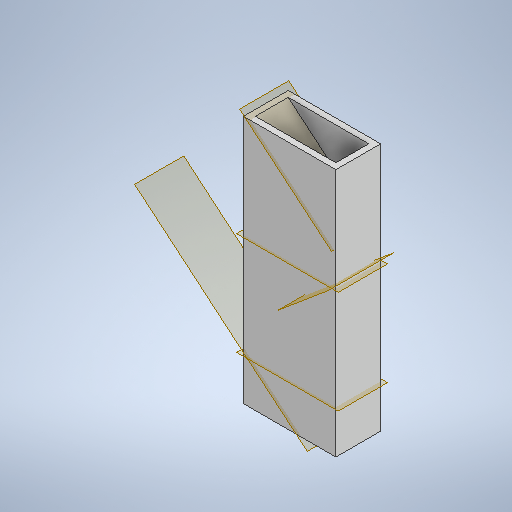
# Autodesk Inventor part: Semesterprojekt1magnetpakholdermedden_med_den_lange_side
Saved by Autodesk Inventor 2027.1 (Build 311270010, 270A)
## iProperties
Created: 2026-10-27
Part Number: Semesterprojekt1magnetpakholdermedden_med_den_lange_side
Material: Generic
Document SubType Name: Modeling
Designer: Sif Isaksen
Density: 1 g/cm^3
Appearance: Default
Author: Sif Isaksen
Autodesk Inventor part; units mm, degrees
ref_plane "YZ Plane" through (0, 0, 0) normal (1, 0, 0) x (0, 1, 0)
ref_plane "XZ Plane" through (0, 0, 0) normal (0, 1, 0) x (-1, 0, 0)
ref_plane "XY Plane" through (0, 0, 0) normal (0, 0, 1) x (1, 0, 0)
sketch "Sketch1" plane through (0, 0, 0) normal (0, 1, 0) x (-1, 0, 0)
  line L0 (11.8062, 10.4849) -> (-15.1938, 10.4849)
  line L1 (-15.1938, 10.4849) -> (-15.1938, -0.5151)
  line L2 (-15.1938, -0.5151) -> (11.8062, -0.5151)
  line L3 (11.8062, -0.5151) -> (11.8062, 10.4849)
  line L4 (13.8062, 12.4849) -> (-17.1938, 12.4849)
  line L5 (-17.1938, 12.4849) -> (-17.1938, -2.5151)
  line L6 (-17.1938, -2.5151) -> (13.8062, -2.5151)
  line L7 (13.8062, -2.5151) -> (13.8062, 12.4849)
  point P0 (0, 0)
  dimension "d0" = 27
  dimension "d1" = 11
  dimension "d2" = 31
  dimension "d3" = 15
  dimension "d4" = 2
  dimension "d5" = 2
  constraints: 16 end point, 4 parallel, 2 horizontal, 2 perpendicular
  measures "d0" distance of L2.end L1.end
  measures "d1" distance of L1.end L0.end
  measures "d2" distance of L6.end L5.end
  measures "d3" distance of L5.end L4.end
  measures "d4" distance between parallel lines of L3 L7
  measures "d5" distance between parallel lines of L4 L0
extrude "Extrusion1" add sketch "Sketch1" along normal blind 20 and the other way blind 63.5
ref_plane "Work Plane1" through (-11.8062, 20, 10.4849) normal (0.6428, 0.766, 0) x (0, 0, -1)
sketch "Sketch2" plane through (-11.8062, 20, 10.4849) normal (0.6428, 0.766, 0) x (0, 0, -1)
  line L0 (0, 0) -> (11, 0) projected
  line L1 (0, 0) -> (11, 0)
  line L2 (11, 0) -> (11, -21)
  line L3 (11, -21) -> (0, -21)
  line L4 (0, -21) -> (0, 0)
  point P0 (10.4849, -21.8998)
  dimension "d9" = 11
  dimension "d10" = 21
  constraints: 8 end point, 2 parallel, 1 horizontal, 1 perpendicular
  measures "d9" distance of L2.end L3.end
  measures "d10" distance of L1.end L2.end
extrude "Extrusion2" add sketch "Sketch2" against normal blind 1
sketch "Sketch3" plane through (0, -63.5, 0) normal (0, -1, 0) x (1, 0, 0)
  point P0 (0, 0)
sketch "Sketch4" plane through (0, -63.5, 0) normal (0, -1, 0) x (1, 0, 0)
  point P0 (0, 0)
ref_plane "Work Plane2" through (0, -14.5, 0) normal (0, 1, 0) x (1, 0, 0)
ref_plane "Work Plane5" through (15.1938, -14.5, 10.4849) normal (-0.6428, 0.766, 0) x (0, 0, -1)
sketch "Sketch8" plane through (15.1938, -14.5, 10.4849) normal (-0.6428, 0.766, 0) x (0, 0, -1)
  point P0 (10.4849, 2.3187)
ref_plane "Work Plane6" through (15.1938, -14.5, 10.4849) normal (-0.6428, 0.766, 0) x (0, 0, -1)
sketch "Sketch9" plane through (15.1938, -14.5, 10.4849) normal (-0.6428, 0.766, 0) x (0, 0, -1)
  line L0 (11, 3.5353) -> (11, -22.1762) projected
  line L1 (11, 0) -> (0, 0)
  line L2 (0, 0) -> (0, 21)
  line L3 (0, 21) -> (11, 21)
  line L4 (11, 21) -> (11, 0)
  point P0 (10.4849, 2.3187)
  point P1 (11, 3.5353)
  dimension "d28" = 11
  dimension "d29" = 21
  constraints: 8 end point, 2 parallel, 1 horizontal, 1 perpendicular
  measures "d28" distance of L2.end L3.end
  measures "d29" distance of L1.end L2.end
extrude "Extrusion5" add sketch "Sketch9" against normal blind 1
ref_plane "Work Plane7" through (0, -49, 0) normal (0, 1, 0) x (1, 0, 0)
ref_plane "Work Plane8" through (-11.8062, -49, 7.7349) normal (0.6428, 0.766, 0) x (0, 0, 1)
sketch "Sketch11" plane through (-11.8062, -49, 7.7349) normal (0.6428, 0.766, 0) x (0, 0, 1)
  line L0 (-8.25, 9.3204) -> (-8.25, -43.5132) projected
  line L1 (-8.25, 0) -> (2.75, 0)
  line L2 (2.75, 0) -> (2.75, 21)
  line L3 (2.75, 21) -> (-8.25, 21)
  line L4 (-8.25, 21) -> (-8.25, 0)
  point P0 (-7.7349, -22.4525)
  dimension "d38" = 11
  dimension "d39" = 21
  constraints: 8 end point, 2 parallel, 1 horizontal, 1 perpendicular
  measures "d38" distance of L3.end L2.end
  measures "d39" distance of L2.end L1.end
extrude "Extrusion7" add sketch "Sketch11" against normal blind 1
body "Solid1"
